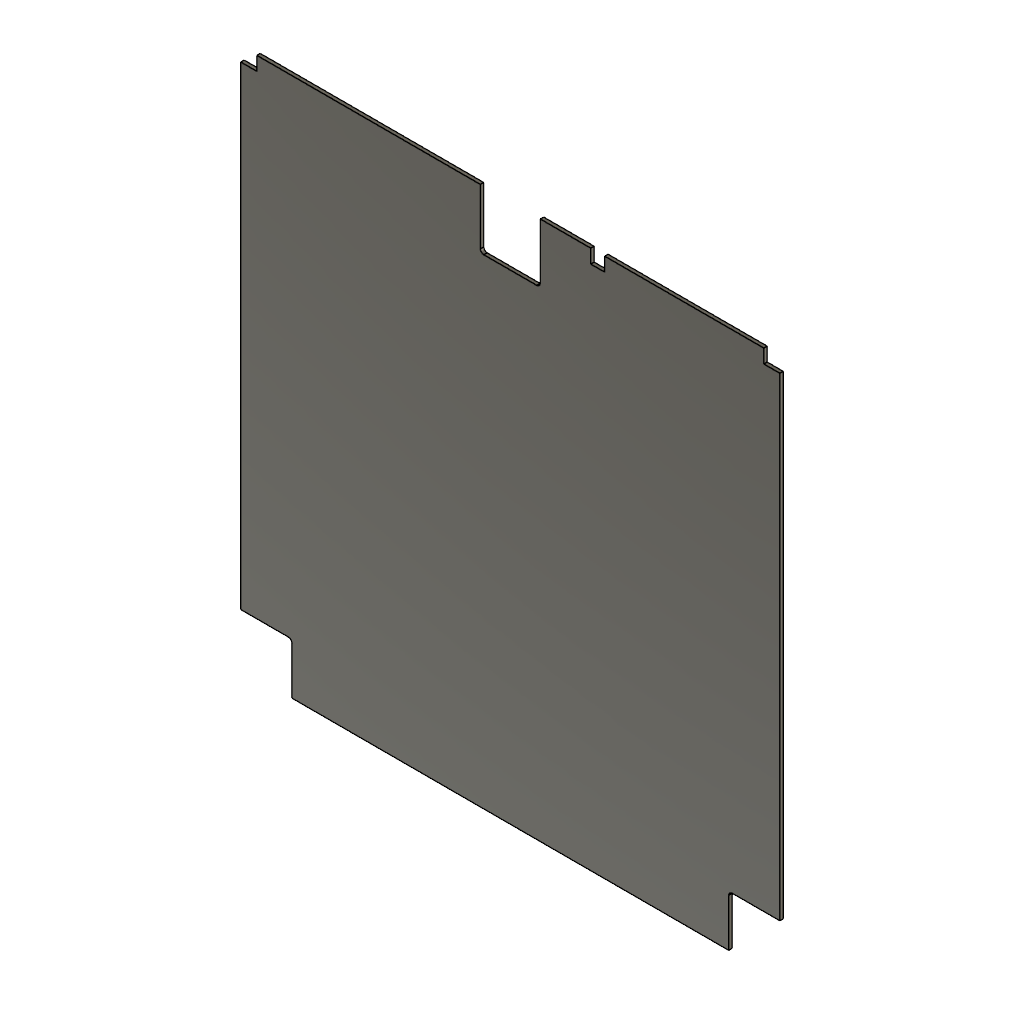
V2_Trident_Panel_Generator (Autodesk Fusion 360 archive; units mm, degrees)
design "Parametric_Panel_Generator"
part number: 2026-10-21-10-21-51-495
part number: 2026-10-21-10-29-37-992
part number: 2026-10-21-10-34-40-831
part number: 2026-10-21-10-38-33-542
part number: 2026-10-21-11-00-50-536
part number: 2026-10-21-11-13-36-842
part number: 2026-10-21-11-22-53-563
part number: 2026-10-21-11-46-04-415
part number: 2026-10-21-11-51-39-561
part number: 2026-10-21-11-54-46-024
part number: 2026-10-21-12-03-15-615
Autodesk Fusion 360 part; units mm, degrees
sketch "Side_Rear_Top_Door" plane through (0, 0, 0) normal (0, 1, 0) x (1, 0, 0)
  line L0 (241.5, -201.5) -> (-241.5, -201.5)
  line L1 (-241.5, -201.5) -> (-241.5, 201.5)
  line L2 (-241.5, 201.5) -> (241.5, 201.5)
  line L3 (241.5, 201.5) -> (241.5, -201.5)
  line L4 (241.5, -201.5) -> (-241.5, 201.5) construction
  line L5 (-241.5, -201.5) -> (241.5, 201.5) construction
  line L6 (241.5, -159) -> (-241.5, -159) construction
  line L7 (0, -201.5) -> (0, 201.5) construction
  line L8 (0, -201.5) -> (0, 201.5) construction
  line L9 (73.5, -201.5) -> (73.5, 201.5) construction
  line L10 (-73.5, -201.5) -> (-73.5, 201.5) construction
  line L11 (73.5, -201.5) -> (73.5, -159) construction
  line L12 (73.5, -159) -> (73.5, -201.5)
  line L13 (73.5, -159) -> (-73.5, -159)
  line L14 (-73.5, -201.5) -> (-73.5, -159)
  line L15 (241.5, 281.5) -> (-241.5, 281.5)
  line L16 (0, -201.5) -> (0, 201.5)
  dimension "d3" = 403
  dimension "d4" = 483
  dimension "d5" = 42.5
  dimension "d6" = 0
  dimension "d7" = 73.5
  dimension "d8" = -73.5
  dimension "d11" = 483
  constraint horizontal L0
  constraint perpendicular L0 L1
  constraint parallel L0 L2
  constraint parallel L1 L3
  constraint coincident L4 origin
  constraint coincident L5 origin
  constraint midpoint L0 L7.start
  constraint midpoint L2 L7.end
  constraint coincident L6 L11.end
  constraint coincident L9 L11.end
  constraint coincident L10 L13.end
  constraint coincident L6 L13.end
  constraint equal L0 L6
  constraint coincident L3 L6.start
  constraint coincident L2 L10.end
  constraint coincident L2 L9.end
  constraint coincident L0 L10.start
  constraint coincident L0 L9.start
  constraint coincident L1 L15.end
  constraint coincident L3 L15.start
  constraint coincident L2 L7.end
  constraint coincident L0 L7.start
  measures "d3" distance of L0.end L1.end
  measures "d4" distance of L1 L3
  measures "d6" distance of L7
  measures "d11" distance of L0
sketch "Deck" plane through (0, 0, 0) normal (0, 1, 0) x (-1, 0, 0)
  line L0 (-234.5, -234.5) -> (234.5, -234.5)
  line L1 (234.5, -234.5) -> (234.5, 234.5)
  line L2 (234.5, 234.5) -> (-234.5, 234.5)
  line L3 (-234.5, 234.5) -> (-234.5, -234.5)
  line L4 (-234.5, -234.5) -> (234.5, 234.5) construction
  line L5 (234.5, -234.5) -> (-234.5, 234.5) construction
  line L6 (0, 234.5) -> (0, -234.5) construction
  line L7 (0, 234.5) -> (0, 224.5) construction
  line L8 (-10, 214.5) -> (10, 214.5)
  line L9 (10, 214.5) -> (10, 234.5)
  line L10 (10, 234.5) -> (-10, 234.5)
  line L11 (-10, 234.5) -> (-10, 214.5)
  line L12 (-10, 214.5) -> (10, 234.5) construction
  line L13 (10, 214.5) -> (-10, 234.5) construction
  line L14 (215, -234.5) -> (215, 234.5)
  line L15 (-215, 234.5) -> (-215, -234.5)
  line L16 (-234.5, -200) -> (234.5, -200)
  line L17 (234.5, 200) -> (-234.5, 200)
  line L18 (0, 214.5) -> (0, 144.5) construction
  circle A0 centre (0, 144.5) radius 7.5
  line L19 (-75, 234.5) -> (-75, -234.5) construction
  line L20 (75, 234.5) -> (75, -234.5) construction
  line L21 (0, 0) -> (-75, 0) construction
  line L22 (0, 60) -> (-75, 60) construction
  line L23 (-78, 52) -> (-72, 52)
  line L24 (-70, 54) -> (-70, 66)
  line L25 (-72, 68) -> (-78, 68)
  line L26 (-80, 66) -> (-80, 54)
  line L27 (-80, 52) -> (-70, 68) construction
  line L28 (-70, 52) -> (-80, 68) construction
  arc A1 (-70, 66) -> (-72, 68) centre (-72, 66) ccw
  arc A2 (-72, 52) -> (-70, 54) centre (-72, 54) ccw
  arc A3 (-80, 54) -> (-78, 52) centre (-78, 54) ccw
  arc A4 (-78, 68) -> (-80, 66) centre (-78, 66) ccw
  line L29 (80, 66) -> (80, 54)
  arc A5 (78, 52) -> (80, 54) centre (78, 54) ccw
  line L30 (78, 52) -> (72, 52)
  arc A6 (70, 54) -> (72, 52) centre (72, 54) ccw
  line L31 (70, 54) -> (70, 66)
  arc A7 (72, 68) -> (70, 66) centre (72, 66) ccw
  arc A8 (80, 66) -> (78, 68) centre (78, 66) ccw
  line L32 (72, 68) -> (78, 68)
  arc A9 (70, -66) -> (72, -68) centre (72, -66) ccw
  line L33 (72, -68) -> (78, -68)
  arc A10 (78, -68) -> (80, -66) centre (78, -66) ccw
  line L34 (80, -66) -> (80, -54)
  arc A11 (80, -54) -> (78, -52) centre (78, -54) ccw
  line L35 (78, -52) -> (72, -52)
  arc A12 (72, -52) -> (70, -54) centre (72, -54) ccw
  line L36 (70, -54) -> (70, -66)
  line L37 (-72, -68) -> (-78, -68)
  arc A13 (-80, -66) -> (-78, -68) centre (-78, -66) ccw
  line L38 (-80, -66) -> (-80, -54)
  arc A14 (-78, -52) -> (-80, -54) centre (-78, -54) ccw
  line L39 (-78, -52) -> (-72, -52)
  arc A15 (-70, -54) -> (-72, -52) centre (-72, -54) ccw
  arc A16 (-72, -68) -> (-70, -66) centre (-72, -66) ccw
  line L40 (-70, -54) -> (-70, -66)
  line L41 (-234.5, -234.5) -> (-190, -234.5)
  line L42 (-190, -234.5) -> (-190, -190)
  line L43 (-190, -190) -> (-234.5, -190)
  line L44 (-234.5, -190) -> (-234.5, -234.5)
  line L45 (190, -190) -> (234.5, -190)
  line L46 (190, -234.5) -> (190, -190)
  line L47 (-234.5, 234.5) -> (-220.5, 234.5)
  line L48 (-220.5, 234.5) -> (-220.5, 222.5)
  line L49 (-220.5, 222.5) -> (-234.5, 222.5)
  line L50 (-234.5, 222.5) -> (-234.5, 234.5)
  line L51 (220.5, 222.5) -> (234.5, 222.5)
  line L52 (220.5, 234.5) -> (220.5, 222.5)
  line L53 (0, 234.5) -> (0, 183)
  line L54 (0, 183) -> (26, 183)
  line L55 (26, 183) -> (-26, 183)
  line L56 (-26, 183) -> (-26, 234.5)
  line L57 (-26, 234.5) -> (26, 234.5)
  line L58 (26, 234.5) -> (26, 183)
  line L59 (0, 234.5) -> (0, 226)
  line L60 (0, 226) -> (-39, 226)
  line L61 (-39, 226) -> (-39, 234.5)
  line L62 (-39, 234.5) -> (0, 234.5)
  line L63 (0, 234.5) -> (0, 226)
  line L64 (39, 226) -> (39, 234.5)
  line L65 (0, 226) -> (39, 226)
  line L66 (-39, 234.5) -> (-70, 234.5)
  line L67 (-70, 234.5) -> (-82, 234.5)
  line L68 (-82, 234.5) -> (-82, 222.5)
  line L69 (-82, 222.5) -> (-70, 222.5)
  line L70 (-70, 222.5) -> (-70, 234.5)
  point P0 (0, 224.5)
  point P1 (-75, 60)
  dimension "d20" = 469
  dimension "d21" = 469
  dimension "d22" = 10
  dimension "d23" = 20
  dimension "d24" = 20
  dimension "d25" = -19.5
  dimension "d26" = -19.5
  dimension "d27" = -34.5
  dimension "d28" = -34.5
  dimension "d29" = 70
  dimension "d30" = 15
  dimension "d31" = 75
  dimension "d32" = -75
  dimension "d33" = 60
  dimension "d34" = 10
  dimension "d35" = 16
  dimension "d36" = 5
  dimension "d37" = 2
  dimension "d83" = 44.5
  dimension "d84" = 44.5
  dimension "d85" = 14
  dimension "d86" = 12
  dimension "d87" = 51.5
  dimension "d88" = 26
  dimension "d89" = 52
  dimension "d90" = 51.5
  dimension "d91" = 8.5
  dimension "d92" = 39
  dimension "d93" = 8.5
  dimension "d94" = 31
  dimension "d95" = 12
  dimension "d96" = 12
  constraint horizontal L0
  constraint perpendicular L0 L1
  constraint parallel L0 L2
  constraint parallel L1 L3
  constraint coincident L4 L21.start
  constraint coincident L5 L21.start
  constraint coincident L21.start origin
  constraint midpoint L2 L6.start
  constraint midpoint L0 L6.end
  constraint perpendicular L2 L7
  constraint horizontal L8
  constraint perpendicular L8 L9
  constraint parallel L8 L10
  constraint parallel L9 L11
  constraint coincident L12 P0
  constraint coincident L13 P0
  constraint coincident P0 L7.end
  constraint midpoint L8 L18.start
  constraint perpendicular L8 L18
  constraint coincident L18.end A0.centre
  constraint midpoint L19 L21.end
  constraint perpendicular L19 L21
  constraint horizontal L23
  constraint perpendicular L23 L24
  constraint parallel L23 L25
  constraint parallel L24 L26
  constraint coincident L27 P1
  constraint coincident L28 P1
  constraint coincident P1 L22.end
  constraint coincident L27.end L25
  constraint coincident L27.end L24
  constraint tangent L25 A1
  constraint tangent L24 A1
  constraint coincident L28.start L24
  constraint coincident L28.start L23
  constraint tangent L24 A2
  constraint tangent L23 A2
  constraint equal A1 A2
  constraint coincident L27.start L23
  constraint coincident L27.start L26
  constraint tangent L23 A3
  constraint tangent L26 A3
  constraint equal A1 A3
  constraint coincident L28.end L26
  constraint coincident L28.end L25
  constraint tangent L26 A4
  constraint tangent L25 A4
  constraint equal A1 A4
  constraint symmetric L6 L25.start A7.start
  constraint symmetric L6 L24.end L31.end
  constraint symmetric L6 A1 A7
  constraint symmetric L6 L24.start A6.start
  constraint symmetric L6 L23.end L30.end
  constraint symmetric L6 A2 A6
  constraint symmetric L6 L23.start A5.start
  constraint symmetric L6 L26.end L29.end
  constraint symmetric L6 A3 A5
  constraint symmetric L6 L26.start L29.start
  constraint symmetric L6 L25.end A8.end
  constraint symmetric L6 A4 A8
  constraint symmetric L21 L25.start L37.start
  constraint symmetric L21 L24.end A16.end
  constraint symmetric L21 A1 A16
  constraint symmetric L21 L24.start A15.start
  constraint symmetric L21 L23.end L39.end
  constraint symmetric L21 A2 A15
  constraint symmetric L21 L23.start A14.start
  constraint symmetric L21 L26.end L38.end
  constraint symmetric L21 A3 A14
  constraint symmetric L21 L26.start A13.start
  constraint symmetric L21 L25.end L37.end
  constraint symmetric L21 A4 A13
  constraint symmetric L21 L29.start A10.end
  constraint symmetric L21 L29.end L34.end
  constraint symmetric L21 A5.start A11.end
  constraint symmetric L21 A5 A11
  constraint symmetric L21 L30.end L35.end
  constraint symmetric L21 A6.start A12.end
  constraint symmetric L21 A6 A12
  constraint symmetric L21 L31.end A9.start
  constraint symmetric L21 A7.start A9.end
  constraint symmetric L21 A7 A9
  constraint symmetric L21 A8.end L33.end
  constraint symmetric L21 A8 A10
  constraint coincident L2 L15.start
  constraint coincident L3 L17.end
  constraint coincident L1 L17.start
  constraint coincident L2 L14.end
  constraint coincident L1 L16.end
  constraint coincident L0 L14.start
  constraint coincident L0 L15.end
  constraint coincident L3 L16.start
  constraint coincident L2 L19.start
  constraint coincident L2 L20.start
  constraint horizontal L41
  constraint vertical L42
  constraint horizontal L43
  constraint vertical L44
  constraint symmetric L6 L41.end L46.start
  constraint symmetric L6 L42.end L45.start
  constraint symmetric L6 L43.end L45.end
  constraint horizontal L47
  constraint vertical L48
  constraint horizontal L49
  constraint vertical L50
  constraint symmetric L6 L47.end L52.start
  constraint symmetric L6 L48.end L51.start
  constraint symmetric L6 L49.end L51.end
  constraint perpendicular L17 L53
  constraint perpendicular L53 L54
  constraint horizontal L55
  constraint vertical L56
  constraint horizontal L57
  constraint vertical L58
  constraint parallel L7 L59
  constraint horizontal L60
  constraint vertical L61
  constraint horizontal L62
  constraint vertical L63
  constraint symmetric L6 L59.end L60.start
  constraint symmetric L6 L60.end L64.start
  constraint symmetric L6 L61.end L64.end
  constraint perpendicular L61 L66
  constraint horizontal L67
  constraint vertical L68
  constraint horizontal L69
  constraint vertical L70
  measures "d20" distance of L1.end L2.end
  measures "d21" distance of L0.end L1.end
  measures "d22" distance of L6.start P0
  measures "d23" distance of L9.end L10.end
  measures "d24" distance of L8.end L9.end
  measures "d29" distance of L18.start L18.end
  measures "d30" diameter of A0
  measures "d34" distance of L27.end L28.end
  measures "d35" distance of L28.start L27.end
  measures "d36" distance of L19 L24
  measures "d37" radius of A1
  measures "d83" distance of L41.end L42.end
  measures "d84" distance of L42.end L43.end
  measures "d85" distance of L48.end L49.end
  measures "d86" distance of L47.end L48.end
  measures "d87" distance of L6.start L53.end
  measures "d88" distance of L53.end L54.end
  measures "d89" distance of L54.end L55.end
  measures "d90" distance of L54.end L57.end
  measures "d91" distance of L6.start L59.end
  measures "d92" distance of L59.end L60.end
  measures "d93" distance of L59.end L6.start
  measures "d94" distance of L61.end L66.end
  measures "d95" distance of L66.end L67.end
  measures "d96" distance of L66.end L69.end
sketch "Bottom" plane through (0, 0, 0) normal (0, 1, 0) x (1, 0, 0)
  line L0 (234.5, 234.5) -> (-234.5, 234.5)
  line L1 (-234.5, 234.5) -> (-234.5, -234.5)
  line L2 (-234.5, -234.5) -> (234.5, -234.5)
  line L3 (234.5, -234.5) -> (234.5, 234.5)
  line L4 (234.5, 234.5) -> (-234.5, -234.5) construction
  line L5 (-234.5, 234.5) -> (234.5, -234.5) construction
  line L6 (232.95, 231.95) -> (-232.95, 231.95) construction
  line L7 (-232.95, 231.95) -> (-232.95, -231.95) construction
  line L8 (-232.95, -231.95) -> (232.95, -231.95) construction
  line L9 (232.95, -231.95) -> (232.95, 231.95) construction
  line L10 (232.95, 231.95) -> (-232.95, -231.95) construction
  line L11 (-232.95, 231.95) -> (232.95, -231.95) construction
  circle A0 centre (-232.95, -231.95) radius 21.5
  circle A1 centre (-232.95, 231.95) radius 21.5
  circle A2 centre (232.95, 231.95) radius 21.5
  circle A3 centre (232.95, -231.95) radius 21.5
  line L12 (0, -234.5) -> (0, 0) construction
  line L13 (60, -234.5) -> (60, 0) construction
  line L14 (-60, -234.5) -> (-60, 0) construction
  line L15 (-234.5, -217.5) -> (234.5, -217.5) construction
  line L16 (60, -217.5) -> (-60, -217.5)
  line L17 (-60, -217.5) -> (-60, -234.5)
  line L18 (-60, -234.5) -> (60, -234.5)
  line L19 (60, -234.5) -> (60, -217.5)
  dimension "d46" = 469
  dimension "d47" = 469
  dimension "d48" = 465.9
  dimension "d49" = 463.9
  dimension "d50" = 43
  dimension "d51" = 43
  dimension "d52" = 43
  dimension "d53" = 43
  dimension "d54" = 60
  dimension "d55" = -60
  dimension "d56" = -17
  dimension "d57" = 17
  constraint horizontal L0
  constraint perpendicular L0 L1
  constraint parallel L0 L2
  constraint parallel L1 L3
  constraint coincident L4 L12.end
  constraint coincident L5 L12.end
  constraint coincident L12.end origin
  constraint horizontal L6
  constraint perpendicular L6 L7
  constraint parallel L6 L8
  constraint parallel L7 L9
  constraint coincident L10 L12.end
  constraint coincident L11 L12.end
  constraint coincident L7.end L8.start
  constraint coincident L6.end L7.start
  constraint coincident L6.start L9.end
  constraint coincident L8.end L9.start
  constraint midpoint L2 L12.start
  constraint horizontal L16
  constraint vertical L17
  constraint horizontal L18
  constraint vertical L19
  constraint coincident L15 L16.start
  constraint coincident L13 L16.start
  measures "d46" distance of L1.end L2.end
  measures "d47" distance of L0.end L1.end
  measures "d48" distance of L7.end L8.end
  measures "d49" distance of L6.end L7.end
  measures "d50" diameter of A0
  measures "d51" diameter of A1
  measures "d52" diameter of A2
  measures "d53" diameter of A3
  measures "d57" distance of L16.start L13.start
extrude "Rear_Panel" [suppressed] in component "V2_Rear_Panel"
fillet "Fillet1" [suppressed] in component "V2_Rear_Panel"
sketch "rear_panel_dxf" plane through (0, 3, 0) normal (0, 1, 0) x (-1, 0, 0) in component "V2_Rear_Panel"
  arc A0 (-239.5, 251.5) -> (-241.5, 249.5) centre (-239.5, 249.5) ccw
  line L0 (-241.5, 249.5) -> (-241.5, -249.5)
  arc A1 (-241.5, -249.5) -> (-239.5, -251.5) centre (-239.5, -249.5) ccw
  line L1 (-239.5, -251.5) -> (239.5, -251.5)
  arc A2 (239.5, -251.5) -> (241.5, -249.5) centre (239.5, -249.5) ccw
  line L2 (241.5, -249.5) -> (241.5, 249.5)
  arc A3 (241.5, 249.5) -> (239.5, 251.5) centre (239.5, 249.5) ccw
  line L3 (239.5, 251.5) -> (75.5, 251.5)
  arc A4 (75.5, 251.5) -> (73.5, 249.5) centre (75.5, 249.5) ccw
  line L4 (73.5, 249.5) -> (73.5, 211)
  arc A5 (71.5, 209) -> (73.5, 211) centre (71.5, 211) ccw
  line L5 (71.5, 209) -> (-71.5, 209)
  arc A6 (-73.5, 211) -> (-71.5, 209) centre (-71.5, 211) ccw
  line L6 (-73.5, 211) -> (-73.5, 249.5)
  arc A7 (-73.5, 249.5) -> (-75.5, 251.5) centre (-75.5, 249.5) ccw
  line L7 (-75.5, 251.5) -> (-239.5, 251.5)
extrude "Side_Panel" [suppressed] in component "V2_Side_Panel"
fillet "Fillet1'" [suppressed] in component "V2_Side_Panel"
sketch "side_panel_dxf" plane through (0, 3, 0) normal (0, 1, 0) x (-1, 0, 0) in component "V2_Side_Panel"
  arc A0 (-239.5, 251.5) -> (-241.5, 249.5) centre (-239.5, 249.5) ccw
  line L0 (-241.5, 249.5) -> (-241.5, -249.5)
  arc A1 (-241.5, -249.5) -> (-239.5, -251.5) centre (-239.5, -249.5) ccw
  line L1 (-239.5, -251.5) -> (239.5, -251.5)
  arc A2 (239.5, -251.5) -> (241.5, -249.5) centre (239.5, -249.5) ccw
  line L2 (241.5, -249.5) -> (241.5, 249.5)
  arc A3 (241.5, 249.5) -> (239.5, 251.5) centre (239.5, 249.5) ccw
  line L3 (239.5, 251.5) -> (-239.5, 251.5)
extrude "Extrude1" [suppressed] in component "Top_Panel"
fillet "Fillet1''" [suppressed] in component "Top_Panel"
sketch "Top_Panel_DXF" plane through (0, 3, 0) normal (0, 1, 0) x (-1, 0, 0) in component "Top_Panel"
  line L0 (239.5, 251.5) -> (-239.5, 251.5)
  arc A0 (241.5, 249.5) -> (239.5, 251.5) centre (239.5, 249.5) ccw
  arc A1 (-239.5, 251.5) -> (-241.5, 249.5) centre (-239.5, 249.5) ccw
  line L1 (-241.5, 249.5) -> (-241.5, -229.5)
  arc A2 (-241.5, -229.5) -> (-239.5, -231.5) centre (-239.5, -229.5) ccw
  line L2 (-239.5, -231.5) -> (239.5, -231.5)
  arc A3 (239.5, -231.5) -> (241.5, -229.5) centre (239.5, -229.5) ccw
  line L3 (241.5, -229.5) -> (241.5, 249.5)
extrude "Extrude1'" [suppressed] in component "V2_Deck_Panel"
fillet "Fillet1'''" [suppressed] in component "V2_Deck_Panel"
sketch "deck_panel_dxf" plane through (0, 3, 0) normal (0, 1, 0) x (-1, 0, 0) in component "V2_Deck_Panel"
  arc A0 (-232.5, 200) -> (-234.5, 198) centre (-232.5, 198) ccw
  line L0 (-234.5, 198) -> (-234.5, -198)
  arc A1 (-234.5, -198) -> (-232.5, -200) centre (-232.5, -198) ccw
  line L1 (-232.5, -200) -> (-217, -200)
  arc A2 (-215, -202) -> (-217, -200) centre (-217, -202) ccw
  line L2 (-215, -202) -> (-215, -232.5)
  arc A3 (-215, -232.5) -> (-213, -234.5) centre (-213, -232.5) ccw
  line L3 (-213, -234.5) -> (213, -234.5)
  arc A4 (213, -234.5) -> (215, -232.5) centre (213, -232.5) ccw
  line L4 (215, -232.5) -> (215, -202)
  arc A5 (217, -200) -> (215, -202) centre (217, -202) ccw
  line L5 (217, -200) -> (232.5, -200)
  arc A6 (232.5, -200) -> (234.5, -198) centre (232.5, -198) ccw
  line L6 (234.5, -198) -> (234.5, 198)
  arc A7 (234.5, 198) -> (232.5, 200) centre (232.5, 198) ccw
  line L7 (232.5, 200) -> (217, 200)
  arc A8 (215, 202) -> (217, 200) centre (217, 202) ccw
  line L8 (215, 202) -> (215, 232.5)
  arc A9 (215, 232.5) -> (213, 234.5) centre (213, 232.5) ccw
  line L9 (213, 234.5) -> (12, 234.5)
  arc A10 (12, 234.5) -> (10, 232.5) centre (12, 232.5) ccw
  line L10 (10, 232.5) -> (10, 216.5)
  arc A11 (8, 214.5) -> (10, 216.5) centre (8, 216.5) ccw
  line L11 (8, 214.5) -> (-8, 214.5)
  arc A12 (-10, 216.5) -> (-8, 214.5) centre (-8, 216.5) ccw
  line L12 (-10, 216.5) -> (-10, 232.5)
  arc A13 (-10, 232.5) -> (-12, 234.5) centre (-12, 232.5) ccw
  line L13 (-12, 234.5) -> (-213, 234.5)
  arc A14 (-213, 234.5) -> (-215, 232.5) centre (-213, 232.5) ccw
  line L14 (-215, 232.5) -> (-215, 202)
  arc A15 (-217, 200) -> (-215, 202) centre (-217, 202) ccw
  line L15 (-217, 200) -> (-232.5, 200)
  circle A16 centre (0, 144.5) radius 7.5
  arc A17 (-78, 68) -> (-80, 66) centre (-78, 66) ccw
  line L16 (-78, 68) -> (-72, 68)
  arc A18 (-70, 66) -> (-72, 68) centre (-72, 66) ccw
  line L17 (-70, 66) -> (-70, 54)
  arc A19 (-72, 52) -> (-70, 54) centre (-72, 54) ccw
  line L18 (-72, 52) -> (-78, 52)
  arc A20 (-80, 54) -> (-78, 52) centre (-78, 54) ccw
  line L19 (-80, 54) -> (-80, 66)
  line L20 (70, -66) -> (70, -54)
  arc A21 (72, -52) -> (70, -54) centre (72, -54) ccw
  line L21 (72, -52) -> (78, -52)
  arc A22 (80, -54) -> (78, -52) centre (78, -54) ccw
  line L22 (80, -54) -> (80, -66)
  arc A23 (78, -68) -> (80, -66) centre (78, -66) ccw
  line L23 (78, -68) -> (72, -68)
  arc A24 (70, -66) -> (72, -68) centre (72, -66) ccw
  arc A25 (70, 54) -> (72, 52) centre (72, 54) ccw
  line L24 (70, 54) -> (70, 66)
  arc A26 (72, 68) -> (70, 66) centre (72, 66) ccw
  line L25 (72, 68) -> (78, 68)
  arc A27 (80, 66) -> (78, 68) centre (78, 66) ccw
  line L26 (80, 66) -> (80, 54)
  arc A28 (78, 52) -> (80, 54) centre (78, 54) ccw
  line L27 (78, 52) -> (72, 52)
  arc A29 (-78, -52) -> (-80, -54) centre (-78, -54) ccw
  line L28 (-78, -52) -> (-72, -52)
  arc A30 (-70, -54) -> (-72, -52) centre (-72, -54) ccw
  line L29 (-70, -54) -> (-70, -66)
  arc A31 (-72, -68) -> (-70, -66) centre (-72, -66) ccw
  line L30 (-72, -68) -> (-78, -68)
  arc A32 (-80, -66) -> (-78, -68) centre (-78, -66) ccw
  line L31 (-80, -66) -> (-80, -54)
extrude "Extrude1''" [suppressed] in component "Bottom_Panel"
fillet "Fillet1''''" [suppressed] in component "Bottom_Panel"
sketch "bottom_panel_dxf" plane through (0, 3, 0) normal (0, 1, 0) x (-1, 0, 0) in component "Bottom_Panel"
  arc A0 (182.5383, -160.4539) -> (184.5, -158.4543) centre (182.5, -158.4543) ccw
  line L0 (184.5, -158.4543) -> (184.5, 158.4543)
  arc A1 (184.5, 158.4543) -> (182.5383, 160.4539) centre (182.5, 158.4543) ccw
  arc A2 (161.4559, 182.4532) -> (182.5383, 160.4539) centre (182.95, 181.95) ccw
  arc A3 (161.4559, 182.4532) -> (159.4564, 184.5) centre (159.4564, 182.5) ccw
  line L1 (159.4564, 184.5) -> (62, 184.5)
  arc A4 (62, 184.5) -> (60, 182.5) centre (62, 182.5) ccw
  line L2 (60, 182.5) -> (60, 169.5)
  arc A5 (58, 167.5) -> (60, 169.5) centre (58, 169.5) ccw
  line L3 (58, 167.5) -> (-58, 167.5)
  arc A6 (-60, 169.5) -> (-58, 167.5) centre (-58, 169.5) ccw
  line L4 (-60, 169.5) -> (-60, 182.5)
  arc A7 (-60, 182.5) -> (-62, 184.5) centre (-62, 182.5) ccw
  line L5 (-62, 184.5) -> (-159.4564, 184.5)
  arc A8 (-159.4564, 184.5) -> (-161.4559, 182.4532) centre (-159.4564, 182.5) ccw
  arc A9 (-182.5383, 160.4539) -> (-161.4559, 182.4532) centre (-182.95, 181.95) ccw
  arc A10 (-182.5383, 160.4539) -> (-184.5, 158.4543) centre (-182.5, 158.4543) ccw
  line L6 (-184.5, 158.4543) -> (-184.5, -158.4543)
  arc A11 (-184.5, -158.4543) -> (-182.5383, -160.4539) centre (-182.5, -158.4543) ccw
  arc A12 (-161.4559, -182.4532) -> (-182.5383, -160.4539) centre (-182.95, -181.95) ccw
  arc A13 (-161.4559, -182.4532) -> (-159.4564, -184.5) centre (-159.4564, -182.5) ccw
  line L7 (-159.4564, -184.5) -> (159.4564, -184.5)
  arc A14 (159.4564, -184.5) -> (161.4559, -182.4532) centre (159.4564, -182.5) ccw
  arc A15 (182.5383, -160.4539) -> (161.4559, -182.4532) centre (182.95, -181.95) ccw
extrude "Extrude1'''" [suppressed] in component "Door_Panel"
fillet "Fillet1'''''" [suppressed] in component "Door_Panel"
sketch "door_panel_dxf" plane through (0, 3, 0) normal (0, 1, 0) x (-1, 0, 0) in component "Door_Panel"
  arc A0 (-2, -251.5) -> (0, -249.5) centre (-2, -249.5) ccw
  line L0 (0, -249.5) -> (0, 249.5)
  arc A1 (0, 249.5) -> (-2, 251.5) centre (-2, 249.5) ccw
  line L1 (-2, 251.5) -> (-239.5, 251.5)
  arc A2 (-239.5, 251.5) -> (-241.5, 249.5) centre (-239.5, 249.5) ccw
  line L2 (-241.5, 249.5) -> (-241.5, -249.5)
  arc A3 (-241.5, -249.5) -> (-239.5, -251.5) centre (-239.5, -249.5) ccw
  line L3 (-239.5, -251.5) -> (-2, -251.5)
extrude "Extrude1''''" [suppressed] in component "Trident_Rear_Panel"
fillet "Fillet1''''''" [suppressed] in component "Trident_Rear_Panel"
sketch "trident_rear_panel_dxf" plane through (0, 3, 0) normal (0, 1, 0) x (-1, 0, 0) in component "Trident_Rear_Panel"
  arc A0 (-241.5, -234.5) -> (-239.5, -236.5) centre (-239.5, -234.5) ccw
  line L0 (-239.5, -236.5) -> (239.5, -236.5)
  arc A1 (239.5, -236.5) -> (241.5, -234.5) centre (239.5, -234.5) ccw
  line L1 (241.5, -234.5) -> (241.5, 234.5)
  arc A2 (241.5, 234.5) -> (239.5, 236.5) centre (239.5, 234.5) ccw
  line L2 (239.5, 236.5) -> (75.5, 236.5)
  arc A3 (75.5, 236.5) -> (73.5, 234.5) centre (75.5, 234.5) ccw
  line L3 (73.5, 234.5) -> (73.5, 196)
  arc A4 (71.5, 194) -> (73.5, 196) centre (71.5, 196) ccw
  line L4 (71.5, 194) -> (-71.5, 194)
  arc A5 (-73.5, 196) -> (-71.5, 194) centre (-71.5, 196) ccw
  line L5 (-73.5, 196) -> (-73.5, 234.5)
  arc A6 (-73.5, 234.5) -> (-75.5, 236.5) centre (-75.5, 234.5) ccw
  line L6 (-75.5, 236.5) -> (-239.5, 236.5)
  arc A7 (-239.5, 236.5) -> (-241.5, 234.5) centre (-239.5, 234.5) ccw
  line L7 (-241.5, 234.5) -> (-241.5, -234.5)
extrude "Extrude1'''''" [suppressed] in component "Trident_Side_Panel"
fillet "Fillet1'''''''" [suppressed] in component "Trident_Side_Panel"
sketch "trident_side_panel_dxf" plane through (0, 3, 0) normal (0, 1, 0) x (-1, 0, 0) in component "Trident_Side_Panel"
  arc A0 (239.5, -236.5) -> (241.5, -234.5) centre (239.5, -234.5) ccw
  line L0 (241.5, -234.5) -> (241.5, 234.5)
  arc A1 (241.5, 234.5) -> (239.5, 236.5) centre (239.5, 234.5) ccw
  line L1 (239.5, 236.5) -> (-239.5, 236.5)
  arc A2 (-239.5, 236.5) -> (-241.5, 234.5) centre (-239.5, 234.5) ccw
  line L2 (-241.5, 234.5) -> (-241.5, -234.5)
  arc A3 (-241.5, -234.5) -> (-239.5, -236.5) centre (-239.5, -234.5) ccw
  line L3 (-239.5, -236.5) -> (239.5, -236.5)
extrude "Extrude1''''''" [suppressed] in component "Trident_Door_Panel"
fillet "Fillet1''''''''" [suppressed] in component "Trident_Door_Panel"
sketch "Trident_Door_Panel" plane through (0, 3, 0) normal (0, 1, 0) x (-1, 0, 0) in component "Trident_Door_Panel"
  arc A0 (-2, -236.5) -> (0, -234.5) centre (-2, -234.5) ccw
  line L0 (0, -234.5) -> (0, 234.5)
  arc A1 (0, 234.5) -> (-2, 236.5) centre (-2, 234.5) ccw
  line L1 (-2, 236.5) -> (-239.5, 236.5)
  arc A2 (-239.5, 236.5) -> (-241.5, 234.5) centre (-239.5, 234.5) ccw
  line L2 (-241.5, 234.5) -> (-241.5, -234.5)
  arc A3 (-241.5, -234.5) -> (-239.5, -236.5) centre (-239.5, -234.5) ccw
  line L3 (-239.5, -236.5) -> (-2, -236.5)
extrude "Extrude1'''''''" add sketch "Deck" along normal blind 3 contours L0 L16 L42 L46 | L3 L15 L17 L43 | L14 L15 L16 L17 L42 L43 L45 L46 L54 L55 L56 L58 | L2 L3 L15 L17 L48 L49 | L2 L15 L17 L56 L60 L61 L66 L68 L69 L70 | L1 L14 L17 L45 | L2 L56 L60 L61 L62 | L2 L14 L17 L58 L64 L65 | L1 L2 L14 L17 L51 L52 | L2 L58 L64 L65 | A0 | L23 L24 L25 L26 A1 A2 A3 A4 | L29 A5 L30 A6 L31 A7 A8 L32 | A9 L33 A10 L34 A11 L35 A12 L36 | L37 A13 L38 A14 L39 A15 A16 L40 in component "Trident_Deck_panel"
fillet "Fillet1'''''''''" radius 3 4 edges at (26, 1.5, 183) (-26, 1.5, 183) (-190, 1.5, -190) (190, 1.5, -190) in component "Trident_Deck_panel"
sketch "Sketch1" plane through (0, 3, 0) normal (0, 1, 0) x (-1, 0, 0) in component "Trident_Deck_panel"
  line L0 (-82, 234.5) -> (-220.5, 234.5)
  line L1 (-220.5, 234.5) -> (-220.5, 222.5)
  line L2 (-220.5, 222.5) -> (-234.5, 222.5)
  line L3 (-234.5, 222.5) -> (-234.5, -190)
  line L4 (-234.5, -190) -> (-193, -190)
  arc A0 (-190, -193) -> (-193, -190) centre (-193, -193) ccw
  line L5 (-190, -193) -> (-190, -234.5)
  line L6 (-190, -234.5) -> (190, -234.5)
  line L7 (190, -234.5) -> (190, -193)
  arc A1 (193, -190) -> (190, -193) centre (193, -193) ccw
  line L8 (193, -190) -> (234.5, -190)
  line L9 (234.5, -190) -> (234.5, 222.5)
  line L10 (234.5, 222.5) -> (220.5, 222.5)
  line L11 (220.5, 222.5) -> (220.5, 234.5)
  line L12 (220.5, 234.5) -> (26, 234.5)
  line L13 (26, 234.5) -> (26, 186)
  arc A2 (23, 183) -> (26, 186) centre (23, 186) ccw
  line L14 (23, 183) -> (-23, 183)
  arc A3 (-26, 186) -> (-23, 183) centre (-23, 186) ccw
  line L15 (-26, 186) -> (-26, 234.5)
  line L16 (-26, 234.5) -> (-70, 234.5)
  line L17 (-70, 234.5) -> (-70, 222.5)
  line L18 (-70, 222.5) -> (-82, 222.5)
  line L19 (-82, 222.5) -> (-82, 234.5)
component "Trident_Deck_panel" placed x (1, 0, 0) y (0, 1, 0) z (0, 0, 1) at (0, 0, 0)
equation "Printer_Size_Width = 350 mm"
equation "d3 = 153 mm + Printer_Size_Height"
equation "d4 = 133 mm + Printer_Size_Width"
equation "d7 = ( 147 / 2 ) * 1 mm"
equation "d11 = 133 mm + Printer_Size_Width"
equation "d20 = 119 mm + Printer_Size_Width"
equation "d21 = 119 mm + Printer_Size_Width"
equation "d46 = 119 mm + Printer_Size_Width"
equation "d47 = 119 mm + Printer_Size_Width"
equation "d48 = 119 mm - 3.1 mm + Printer_Size_Width"
equation "d49 = 119 mm - 5.1 mm + Printer_Size_Width"
equation "Printer_Size_Height = 250 mm"
equation "version_number = 'v' + '2'" comment "Version Number"
equation "d88 = ( 52 / 2 ) * 1 mm"
equation "d92 = ( 78 / 2 ) * 1 mm"
